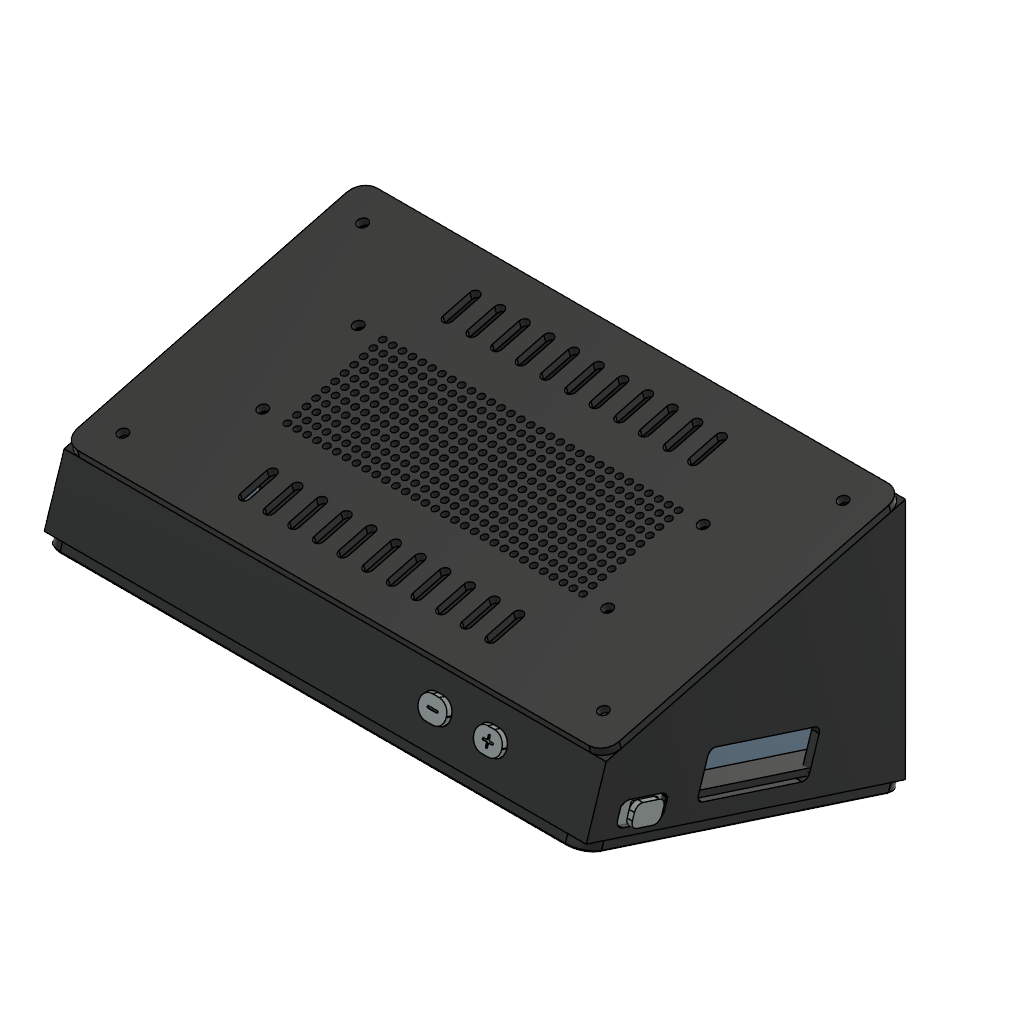
NP2-case-v03 (Autodesk Fusion 360 design; units mm, degrees)
Autodesk Fusion 360 part; units mm, degrees
(part 1 of 2)
sketch "Esboço1" plane through (0, 0, 0) normal (0, 0, 1) x (1, 0, 0) in component "01 / Moldura fina / microfones frontais"
  line L0 (-82, -55) -> (82, -55)
  line L1 (88, -49) -> (88, 49)
  line L2 (82, 55) -> (-82, 55)
  line L3 (-88, 49) -> (-88, -49)
  arc A0 (82, -55) -> (88, -49) centre (82, -49) ccw
  arc A1 (88, 49) -> (82, 55) centre (82, 49) ccw
  arc A2 (-82, 55) -> (-88, 49) centre (-82, 49) ccw
  arc A3 (-88, -49) -> (-82, -55) centre (-82, -49) ccw
extrude "Frente 176 x 110 R6" add sketch "Esboço1" against normal blind 3 makes body 1 in component "01 / Moldura fina / microfones frontais"
fillet "Borda de toque suave" radius 0.5 64 edges at (0, -55, 0) (86.2426, -53.2426, 0) (88, 0, 0) (86.2426, 53.2426, 0) (0, 55, 0) (-86.2426, 53.2426, 0) (-88, 0, 0) (-86.2426, -53.2426, 0) (86.2426, -53.2426, 0) (88, 0, 0) (86.2426, 53.2426, 0) (0, 55, 0) (-86.2426, 53.2426, 0) (-88, 0, 0) (-86.2426, -53.2426, 0) (0, -55, 0) (88, 0, 0) (86.2426, 53.2426, 0) (0, 55, 0) (-86.2426, 53.2426, 0) (-88, 0, 0) (-86.2426, -53.2426, 0) (0, -55, 0) (86.2426, -53.2426, 0) (86.2426, 53.2426, 0) (0, 55, 0) (-86.2426, 53.2426, 0) (-88, 0, 0) (-86.2426, -53.2426, 0) (0, -55, 0) (86.2426, -53.2426, 0) (88, 0, 0) (0, 55, 0) (-86.2426, 53.2426, 0) (-88, 0, 0) (-86.2426, -53.2426, 0) (0, -55, 0) (86.2426, -53.2426, 0) (88, 0, 0) (86.2426, 53.2426, 0) (-86.2426, 53.2426, 0) (-88, 0, 0) (-86.2426, -53.2426, 0) (0, -55, 0) (86.2426, -53.2426, 0) (88, 0, 0) (86.2426, 53.2426, 0) (0, 55, 0) (-88, 0, 0) (-86.2426, -53.2426, 0) (0, -55, 0) (86.2426, -53.2426, 0) (88, 0, 0) (86.2426, 53.2426, 0) (0, 55, 0) (-86.2426, 53.2426, 0) (-86.2426, -53.2426, 0) (0, -55, 0) (86.2426, -53.2426, 0) (88, 0, 0) (86.2426, 53.2426, 0) (0, 55, 0) (-86.2426, 53.2426, 0) (-88, 0, 0) on bodies 1 in component "01 / Moldura fina / microfones frontais"
ref_plane "Plano de trabalho1" through (0, 0, 0.1) normal (0, 0, 1) x (1, 0, 0) in component "01 / Moldura fina / microfones frontais"
sketch "Esboço2" plane through (0, 0, 0.1) normal (0, 0, 1) x (1, 0, 0) in component "01 / Moldura fina / microfones frontais"
  line L0 (-81.84, -49.885) -> (81.84, -49.885)
  line L1 (82.44, -49.285) -> (82.44, 49.285)
  line L2 (81.84, 49.885) -> (-81.84, 49.885)
  line L3 (-82.44, 49.285) -> (-82.44, -49.285)
  arc A0 (81.84, -49.885) -> (82.44, -49.285) centre (81.84, -49.285) ccw
  arc A1 (82.44, 49.285) -> (81.84, 49.885) centre (81.84, 49.285) ccw
  arc A2 (-81.84, 49.885) -> (-82.44, 49.285) centre (-81.84, 49.285) ccw
  arc A3 (-82.44, -49.285) -> (-81.84, -49.885) centre (-81.84, -49.285) ccw
extrude "Janela vidro / folga 0.3 mm por lado" cut sketch "Esboço2" against normal blind 3.3 bodies 1 in component "01 / Moldura fina / microfones frontais"
ref_plane "Plano de trabalho2" through (0, 0, 0.1) normal (0, 0, 1) x (1, 0, 0) in component "01 / Moldura fina / microfones frontais"
sketch "Esboço3" plane through (0, 0, 0.1) normal (0, 0, 1) x (1, 0, 0) in component "01 / Moldura fina / microfones frontais"
  circle A0 centre (-68, -51) radius 0.8
  circle A1 centre (73, -51) radius 0.8
extrude "MIC 1 e MIC 2 / borda inferior" cut sketch "Esboço3" against normal blind 3.3 bodies 1 in component "01 / Moldura fina / microfones frontais"
ref_plane "Plano de trabalho1" through (0, 0, -0.65) normal (0, 0, 1) x (1, 0, 0) in component "REF / Vidro 164.28 x 99.17 / area ativa assimetrica"
sketch "Esboço1 (2)" plane through (0, 0, -0.65) normal (0, 0, 1) x (1, 0, 0) in component "REF / Vidro 164.28 x 99.17 / area ativa assimetrica"
  line L0 (-81.89, -49.585) -> (81.89, -49.585)
  line L1 (82.14, -49.335) -> (82.14, 49.335)
  line L2 (81.89, 49.585) -> (-81.89, 49.585)
  line L3 (-82.14, 49.335) -> (-82.14, -49.335)
  arc A0 (81.89, -49.585) -> (82.14, -49.335) centre (81.89, -49.335) ccw
  arc A1 (82.14, 49.335) -> (81.89, 49.585) centre (81.89, 49.335) ccw
  arc A2 (-81.89, 49.585) -> (-82.14, 49.335) centre (-81.89, 49.335) ccw
  arc A3 (-82.14, -49.335) -> (-81.89, -49.585) centre (-81.89, -49.335) ccw
extrude "Vidro do display" add sketch "Esboço1 (2)" against normal blind 2.15 separate body makes body 2 in component "REF / Vidro 164.28 x 99.17 / area ativa assimetrica"
ref_plane "Plano de trabalho2" through (0, 0, -0.6) normal (0, 0, 1) x (1, 0, 0) in component "REF / Vidro 164.28 x 99.17 / area ativa assimetrica"
sketch "Esboço2 (2)" plane through (0, 0, -0.6) normal (0, 0, 1) x (1, 0, 0) in component "REF / Vidro 164.28 x 99.17 / area ativa assimetrica"
  line L0 (-78.985, -40.855) -> (75.395, -40.855)
  line L1 (75.495, -40.755) -> (75.495, 45.465)
  line L2 (75.395, 45.565) -> (-78.985, 45.565)
  line L3 (-79.085, 45.465) -> (-79.085, -40.755)
  arc A0 (75.395, -40.855) -> (75.495, -40.755) centre (75.395, -40.755) ccw
  arc A1 (75.495, 45.465) -> (75.395, 45.565) centre (75.395, 45.465) ccw
  arc A2 (-78.985, 45.565) -> (-79.085, 45.465) centre (-78.985, 45.465) ccw
  arc A3 (-79.085, -40.755) -> (-78.985, -40.855) centre (-78.985, -40.755) ccw
extrude "Area ativa 154.58 x 86.42" add sketch "Esboço2 (2)" against normal blind 0.04 separate body makes body 3 in component "REF / Vidro 164.28 x 99.17 / area ativa assimetrica"
ref_plane "Plano de trabalho1" through (-88, 0, 0) normal (1, 0, 0) x (0, 1, 0) in component "02 / Corpo em cunha / apoio direto na mesa"
sketch "Esboço1 (3)" plane through (-88, 0, 0) normal (1, 0, 0) x (0, 0, -1) in component "02 / Corpo em cunha / apoio direto na mesa"
  line L0 (3, -54) -> (3, 55)
  line L1 (3, 55) -> (24, 55)
  line L2 (24, 55) -> (78, -29.6563)
  line L3 (78, -29.6563) -> (3, -54)
extrude "Volume externo da cunha" add sketch "Esboço1 (3)" along normal blind 176 separate body makes body 4 in component "02 / Corpo em cunha / apoio direto na mesa"
shell "Paredes 2.4 / frente e traseira abertas" thickness 2.4 removed faces 2 at (-29.3333, -17.6667, -3) at (-29.3333, 26.7812, -42) on bodies 4 in component "02 / Corpo em cunha / apoio direto na mesa"
ref_plane "Plano de trabalho2" through (-88.1, 0, 0) normal (1, 0, 0) x (0, 1, 0) in component "02 / Corpo em cunha / apoio direto na mesa"
sketch "Esboço2 (3)" plane through (-88.1, 0, 0) normal (1, 0, 0) x (0, 0, -1) in component "02 / Corpo em cunha / apoio direto na mesa"
  line L0 (10, -19) -> (20, -19)
  line L1 (22, -17) -> (22, 17)
  line L2 (20, 19) -> (10, 19)
  line L3 (8, 17) -> (8, -17)
  arc A0 (20, -19) -> (22, -17) centre (20, -17) ccw
  arc A1 (22, 17) -> (20, 19) centre (20, 17) ccw
  arc A2 (10, 19) -> (8, 17) centre (10, 17) ccw
  arc A3 (8, -17) -> (10, -19) centre (10, -17) ccw
extrude "Acesso lateral / USB e expansao" cut sketch "Esboço2 (3)" along normal blind 2.8 bodies 4 in component "02 / Corpo em cunha / apoio direto na mesa"
ref_plane "Plano de trabalho3" through (88.1, 0, 0) normal (1, 0, 0) x (0, 1, 0) in component "02 / Corpo em cunha / apoio direto na mesa"
sketch "Esboço3 (2)" plane through (88.1, 0, 0) normal (1, 0, 0) x (0, 0, -1) in component "02 / Corpo em cunha / apoio direto na mesa"
  line L0 (10, -19) -> (20, -19)
  line L1 (22, -17) -> (22, 17)
  line L2 (20, 19) -> (10, 19)
  line L3 (8, 17) -> (8, -17)
  arc A0 (20, -19) -> (22, -17) centre (20, -17) ccw
  arc A1 (22, 17) -> (20, 19) centre (20, 17) ccw
  arc A2 (10, 19) -> (8, 17) centre (10, 17) ccw
  arc A3 (8, -17) -> (10, -19) centre (10, -17) ccw
extrude "Acesso lateral / USB e expansao (1)" cut sketch "Esboço3 (2)" against normal blind 2.8 bodies 4 in component "02 / Corpo em cunha / apoio direto na mesa"
ref_plane "Plano de trabalho4" through (0, 55.1, 0) normal (0, 1, 0) x (0, 0, 1) in component "02 / Corpo em cunha / apoio direto na mesa"
sketch "Esboço4" plane through (0, 55.1, 0) normal (0, 1, 0) x (1, 0, 0) in component "02 / Corpo em cunha / apoio direto na mesa"
  line L0 (34.8, 10.2) -> (37.2, 10.2)
  line L1 (40.8, 13.8) -> (40.8, 14.2)
  line L2 (37.2, 17.8) -> (34.8, 17.8)
  line L3 (31.2, 14.2) -> (31.2, 13.8)
  arc A0 (37.2, 10.2) -> (40.8, 13.8) centre (37.2, 13.8) ccw
  arc A1 (40.8, 14.2) -> (37.2, 17.8) centre (37.2, 14.2) ccw
  arc A2 (34.8, 17.8) -> (31.2, 14.2) centre (34.8, 14.2) ccw
  arc A3 (31.2, 13.8) -> (34.8, 10.2) centre (34.8, 13.8) ccw
extrude "Janela tecla volume" cut sketch "Esboço4" against normal blind 2.7 bodies 4 in component "02 / Corpo em cunha / apoio direto na mesa"
ref_plane "Plano de trabalho5" through (0, 55.1, 0) normal (0, 1, 0) x (0, 0, 1) in component "02 / Corpo em cunha / apoio direto na mesa"
sketch "Esboço5" plane through (0, 55.1, 0) normal (0, 1, 0) x (1, 0, 0) in component "02 / Corpo em cunha / apoio direto na mesa"
  line L0 (52.8, 10.2) -> (55.2, 10.2)
  line L1 (58.8, 13.8) -> (58.8, 14.2)
  line L2 (55.2, 17.8) -> (52.8, 17.8)
  line L3 (49.2, 14.2) -> (49.2, 13.8)
  arc A0 (55.2, 10.2) -> (58.8, 13.8) centre (55.2, 13.8) ccw
  arc A1 (58.8, 14.2) -> (55.2, 17.8) centre (55.2, 14.2) ccw
  arc A2 (52.8, 17.8) -> (49.2, 14.2) centre (52.8, 14.2) ccw
  arc A3 (49.2, 13.8) -> (52.8, 10.2) centre (52.8, 13.8) ccw
extrude "Janela tecla volume (1)" cut sketch "Esboço5" against normal blind 2.7 bodies 4 in component "02 / Corpo em cunha / apoio direto na mesa"
ref_plane "Plano de trabalho6" through (88.1, 0, 0) normal (1, 0, 0) x (0, 1, 0) in component "02 / Corpo em cunha / apoio direto na mesa"
sketch "Esboço6" plane through (88.1, 0, 0) normal (1, 0, 0) x (0, 0, -1) in component "02 / Corpo em cunha / apoio direto na mesa"
  line L0 (7.8, 29.82) -> (10.2, 29.82)
  line L1 (12.6, 32.22) -> (12.6, 43.42)
  line L2 (10.2, 45.82) -> (7.8, 45.82)
  line L3 (5.4, 43.42) -> (5.4, 32.22)
  arc A0 (10.2, 29.82) -> (12.6, 32.22) centre (10.2, 32.22) ccw
  arc A1 (12.6, 43.42) -> (10.2, 45.82) centre (10.2, 43.42) ccw
  arc A2 (7.8, 45.82) -> (5.4, 43.42) centre (7.8, 43.42) ccw
  arc A3 (5.4, 32.22) -> (7.8, 29.82) centre (7.8, 32.22) ccw
extrude "Janela chave ON OFF original" cut sketch "Esboço6" against normal blind 2.7 bodies 4 in component "02 / Corpo em cunha / apoio direto na mesa"
sketch "Esboço1 (4)" plane through (0, 0, 0) normal (0, 0, 1) x (1, 0, 0) in component "03 / Tampa traseira / grelha alto-falante + ventilacao"
  point P0 (-10, 0)
  point P1 (10, 0)
  point P2 (0, 20)
ref_plane "Plano de trabalho1" through (-10, 0, -59.0831) normal (0, -0.537781, 0.843084) x (1, 0, 0) in component "03 / Tampa traseira / grelha alto-falante + ventilacao"
sketch "Esboço2 (4)" plane through (0, 26.788, -41.9957) normal (0, -0.537781, 0.843084) x (1, 0, 0) in component "03 / Tampa traseira / grelha alto-falante + ventilacao"
  line L0 (-83, -66.9497) -> (83, -66.9497)
  line L1 (88, -61.9497) -> (88, 28.4629)
  line L2 (83, 33.4629) -> (-83, 33.4629)
  line L3 (-88, 28.4629) -> (-88, -61.9497)
  arc A0 (83, -66.9497) -> (88, -61.9497) centre (83, -61.9497) ccw
  arc A1 (88, 28.4629) -> (83, 33.4629) centre (83, 28.4629) ccw
  arc A2 (-83, 33.4629) -> (-88, 28.4629) centre (-83, 28.4629) ccw
  arc A3 (-88, -61.9497) -> (-83, -66.9497) centre (-83, -61.9497) ccw
extrude "Tampa traseira removivel" add sketch "Esboço2 (4)" against normal blind 2.4 separate body makes body 5 in component "03 / Tampa traseira / grelha alto-falante + ventilacao"
sketch "Esboço3 (3)" plane through (0, 0, 0) normal (0, 0, 1) x (1, 0, 0) in component "03 / Tampa traseira / grelha alto-falante + ventilacao"
  point P0 (-10, 0)
  point P1 (10, 0)
  point P2 (0, 20)
ref_plane "Plano de trabalho2" through (-10, 0, -59.0831) normal (0, -0.537781, 0.843084) x (1, 0, 0) in component "03 / Tampa traseira / grelha alto-falante + ventilacao"
ref_plane "Plano de trabalho3" through (-10, -0.0538, -58.9987) normal (0, -0.537781, 0.843084) x (1, 0, 0) in component "03 / Tampa traseira / grelha alto-falante + ventilacao"
sketch "Esboço4 (2)" plane through (0, 26.7342, -41.9114) normal (0, -0.537781, 0.843084) x (1, 0, 0) in component "03 / Tampa traseira / grelha alto-falante + ventilacao"
  circle A0 centre (-35.2, -24.7434) radius 1
  circle A1 centre (-32, -24.7434) radius 1
  circle A2 centre (-28.8, -24.7434) radius 1
  circle A3 centre (-25.6, -24.7434) radius 1
  circle A4 centre (-22.4, -24.7434) radius 1
  circle A5 centre (-19.2, -24.7434) radius 1
  circle A6 centre (-16, -24.7434) radius 1
  circle A7 centre (-12.8, -24.7434) radius 1
  circle A8 centre (-9.6, -24.7434) radius 1
  circle A9 centre (-6.4, -24.7434) radius 1
  circle A10 centre (-3.2, -24.7434) radius 1
  circle A11 centre (0, -24.7434) radius 1
  circle A12 centre (3.2, -24.7434) radius 1
  circle A13 centre (6.4, -24.7434) radius 1
  circle A14 centre (9.6, -24.7434) radius 1
  circle A15 centre (12.8, -24.7434) radius 1
  circle A16 centre (16, -24.7434) radius 1
  circle A17 centre (19.2, -24.7434) radius 1
  circle A18 centre (22.4, -24.7434) radius 1
  circle A19 centre (25.6, -24.7434) radius 1
  circle A20 centre (28.8, -24.7434) radius 1
  circle A21 centre (32, -24.7434) radius 1
  circle A22 centre (35.2, -24.7434) radius 1
  circle A23 centre (-35.2, -21.5434) radius 1
  circle A24 centre (-32, -21.5434) radius 1
  circle A25 centre (-28.8, -21.5434) radius 1
  circle A26 centre (-25.6, -21.5434) radius 1
  circle A27 centre (-22.4, -21.5434) radius 1
  circle A28 centre (-19.2, -21.5434) radius 1
  circle A29 centre (-16, -21.5434) radius 1
  circle A30 centre (-12.8, -21.5434) radius 1
  circle A31 centre (-9.6, -21.5434) radius 1
  circle A32 centre (-6.4, -21.5434) radius 1
  circle A33 centre (-3.2, -21.5434) radius 1
  circle A34 centre (0, -21.5434) radius 1
  circle A35 centre (3.2, -21.5434) radius 1
  circle A36 centre (6.4, -21.5434) radius 1
  circle A37 centre (9.6, -21.5434) radius 1
  circle A38 centre (12.8, -21.5434) radius 1
  circle A39 centre (16, -21.5434) radius 1
  circle A40 centre (19.2, -21.5434) radius 1
  circle A41 centre (22.4, -21.5434) radius 1
  circle A42 centre (25.6, -21.5434) radius 1
  circle A43 centre (28.8, -21.5434) radius 1
  circle A44 centre (32, -21.5434) radius 1
  circle A45 centre (35.2, -21.5434) radius 1
  circle A46 centre (-35.2, -18.3434) radius 1
  circle A47 centre (-32, -18.3434) radius 1
  circle A48 centre (-28.8, -18.3434) radius 1
  circle A49 centre (-25.6, -18.3434) radius 1
  circle A50 centre (-22.4, -18.3434) radius 1
  circle A51 centre (-19.2, -18.3434) radius 1
  circle A52 centre (-16, -18.3434) radius 1
  circle A53 centre (-12.8, -18.3434) radius 1
  circle A54 centre (-9.6, -18.3434) radius 1
  circle A55 centre (-6.4, -18.3434) radius 1
  circle A56 centre (-3.2, -18.3434) radius 1
  circle A57 centre (0, -18.3434) radius 1
  circle A58 centre (3.2, -18.3434) radius 1
  circle A59 centre (6.4, -18.3434) radius 1
  circle A60 centre (9.6, -18.3434) radius 1
  circle A61 centre (12.8, -18.3434) radius 1
  circle A62 centre (16, -18.3434) radius 1
  circle A63 centre (19.2, -18.3434) radius 1
  circle A64 centre (22.4, -18.3434) radius 1
  circle A65 centre (25.6, -18.3434) radius 1
  circle A66 centre (28.8, -18.3434) radius 1
  circle A67 centre (32, -18.3434) radius 1
  circle A68 centre (35.2, -18.3434) radius 1
  circle A69 centre (-35.2, -15.1434) radius 1
  circle A70 centre (-32, -15.1434) radius 1
  circle A71 centre (-28.8, -15.1434) radius 1
  circle A72 centre (-25.6, -15.1434) radius 1
  circle A73 centre (-22.4, -15.1434) radius 1
  circle A74 centre (-19.2, -15.1434) radius 1
  circle A75 centre (-16, -15.1434) radius 1
  circle A76 centre (-12.8, -15.1434) radius 1
  circle A77 centre (-9.6, -15.1434) radius 1
  circle A78 centre (-6.4, -15.1434) radius 1
  circle A79 centre (-3.2, -15.1434) radius 1
  circle A80 centre (0, -15.1434) radius 1
  circle A81 centre (3.2, -15.1434) radius 1
  circle A82 centre (6.4, -15.1434) radius 1
  circle A83 centre (9.6, -15.1434) radius 1
  circle A84 centre (12.8, -15.1434) radius 1
  circle A85 centre (16, -15.1434) radius 1
  circle A86 centre (19.2, -15.1434) radius 1
  circle A87 centre (22.4, -15.1434) radius 1
  circle A88 centre (25.6, -15.1434) radius 1
  circle A89 centre (28.8, -15.1434) radius 1
  circle A90 centre (32, -15.1434) radius 1
  circle A91 centre (35.2, -15.1434) radius 1
  circle A92 centre (-35.2, -11.9434) radius 1
  circle A93 centre (-32, -11.9434) radius 1
  circle A94 centre (-28.8, -11.9434) radius 1
  circle A95 centre (-25.6, -11.9434) radius 1
  circle A96 centre (-22.4, -11.9434) radius 1
  circle A97 centre (-19.2, -11.9434) radius 1
  circle A98 centre (-16, -11.9434) radius 1
  circle A99 centre (-12.8, -11.9434) radius 1
  circle A100 centre (-9.6, -11.9434) radius 1
  circle A101 centre (-6.4, -11.9434) radius 1
  circle A102 centre (-3.2, -11.9434) radius 1
  circle A103 centre (0, -11.9434) radius 1
  circle A104 centre (3.2, -11.9434) radius 1
  circle A105 centre (6.4, -11.9434) radius 1
  circle A106 centre (9.6, -11.9434) radius 1
  circle A107 centre (12.8, -11.9434) radius 1
  circle A108 centre (16, -11.9434) radius 1
  circle A109 centre (19.2, -11.9434) radius 1
  circle A110 centre (22.4, -11.9434) radius 1
  circle A111 centre (25.6, -11.9434) radius 1
  circle A112 centre (28.8, -11.9434) radius 1
  circle A113 centre (32, -11.9434) radius 1
  circle A114 centre (35.2, -11.9434) radius 1
  circle A115 centre (-35.2, -8.7434) radius 1
  circle A116 centre (-32, -8.7434) radius 1
  circle A117 centre (-28.8, -8.7434) radius 1
  circle A118 centre (-25.6, -8.7434) radius 1
  circle A119 centre (-22.4, -8.7434) radius 1
  circle A120 centre (-19.2, -8.7434) radius 1
  circle A121 centre (-16, -8.7434) radius 1
  circle A122 centre (-12.8, -8.7434) radius 1
  circle A123 centre (-9.6, -8.7434) radius 1
  circle A124 centre (-6.4, -8.7434) radius 1
  circle A125 centre (-3.2, -8.7434) radius 1
  circle A126 centre (0, -8.7434) radius 1
  circle A127 centre (3.2, -8.7434) radius 1
  circle A128 centre (6.4, -8.7434) radius 1
  circle A129 centre (9.6, -8.7434) radius 1
  circle A130 centre (12.8, -8.7434) radius 1
  circle A131 centre (16, -8.7434) radius 1
  circle A132 centre (19.2, -8.7434) radius 1
  circle A133 centre (22.4, -8.7434) radius 1
  circle A134 centre (25.6, -8.7434) radius 1
  circle A135 centre (28.8, -8.7434) radius 1
  circle A136 centre (32, -8.7434) radius 1
  circle A137 centre (35.2, -8.7434) radius 1
sketch "Esboço5 (2)" plane through (0, 0, 0) normal (0, 0, 1) x (1, 0, 0) in component "03 / Tampa traseira / grelha alto-falante + ventilacao"
  point P0 (-10, 0)
  point P1 (10, 0)
  point P2 (0, 20)
ref_plane "Plano de trabalho4" through (-10, 0, -59.0831) normal (0, -0.537781, 0.843084) x (1, 0, 0) in component "03 / Tampa traseira / grelha alto-falante + ventilacao"
ref_plane "Plano de trabalho5" through (-10, -0.0538, -58.9987) normal (0, -0.537781, 0.843084) x (1, 0, 0) in component "03 / Tampa traseira / grelha alto-falante + ventilacao"
sketch "Esboço6 (2)" plane through (0, 26.7342, -41.9114) normal (0, -0.537781, 0.843084) x (1, 0, 0) in component "03 / Tampa traseira / grelha alto-falante + ventilacao"
  line L0 (-40, -56.7434) -> (-40, -56.7434)
  line L1 (-38.5, -55.2434) -> (-38.5, -46.2434)
  line L2 (-40, -44.7434) -> (-40, -44.7434)
  line L3 (-41.5, -46.2434) -> (-41.5, -55.2434)
  arc A0 (-40, -56.7434) -> (-38.5, -55.2434) centre (-40, -55.2434) ccw
  arc A1 (-38.5, -46.2434) -> (-40, -44.7434) centre (-40, -46.2434) ccw
  arc A2 (-40, -44.7434) -> (-41.5, -46.2434) centre (-40, -46.2434) ccw
  arc A3 (-41.5, -55.2434) -> (-40, -56.7434) centre (-40, -55.2434) ccw
  line L4 (-32, -56.7434) -> (-32, -56.7434)
  line L5 (-30.5, -55.2434) -> (-30.5, -46.2434)
  line L6 (-32, -44.7434) -> (-32, -44.7434)
  line L7 (-33.5, -46.2434) -> (-33.5, -55.2434)
  arc A4 (-32, -56.7434) -> (-30.5, -55.2434) centre (-32, -55.2434) ccw
  arc A5 (-30.5, -46.2434) -> (-32, -44.7434) centre (-32, -46.2434) ccw
  arc A6 (-32, -44.7434) -> (-33.5, -46.2434) centre (-32, -46.2434) ccw
  arc A7 (-33.5, -55.2434) -> (-32, -56.7434) centre (-32, -55.2434) ccw
  line L8 (-24, -56.7434) -> (-24, -56.7434)
  line L9 (-22.5, -55.2434) -> (-22.5, -46.2434)
  line L10 (-24, -44.7434) -> (-24, -44.7434)
  line L11 (-25.5, -46.2434) -> (-25.5, -55.2434)
  arc A8 (-24, -56.7434) -> (-22.5, -55.2434) centre (-24, -55.2434) ccw
  arc A9 (-22.5, -46.2434) -> (-24, -44.7434) centre (-24, -46.2434) ccw
  arc A10 (-24, -44.7434) -> (-25.5, -46.2434) centre (-24, -46.2434) ccw
  arc A11 (-25.5, -55.2434) -> (-24, -56.7434) centre (-24, -55.2434) ccw
  line L12 (-16, -56.7434) -> (-16, -56.7434)
  line L13 (-14.5, -55.2434) -> (-14.5, -46.2434)
  line L14 (-16, -44.7434) -> (-16, -44.7434)
  line L15 (-17.5, -46.2434) -> (-17.5, -55.2434)
  arc A12 (-16, -56.7434) -> (-14.5, -55.2434) centre (-16, -55.2434) ccw
  arc A13 (-14.5, -46.2434) -> (-16, -44.7434) centre (-16, -46.2434) ccw
  arc A14 (-16, -44.7434) -> (-17.5, -46.2434) centre (-16, -46.2434) ccw
  arc A15 (-17.5, -55.2434) -> (-16, -56.7434) centre (-16, -55.2434) ccw
  line L16 (-8, -56.7434) -> (-8, -56.7434)
  line L17 (-6.5, -55.2434) -> (-6.5, -46.2434)
  line L18 (-8, -44.7434) -> (-8, -44.7434)
  line L19 (-9.5, -46.2434) -> (-9.5, -55.2434)
  arc A16 (-8, -56.7434) -> (-6.5, -55.2434) centre (-8, -55.2434) ccw
  arc A17 (-6.5, -46.2434) -> (-8, -44.7434) centre (-8, -46.2434) ccw
  arc A18 (-8, -44.7434) -> (-9.5, -46.2434) centre (-8, -46.2434) ccw
  arc A19 (-9.5, -55.2434) -> (-8, -56.7434) centre (-8, -55.2434) ccw
  line L20 (0, -56.7434) -> (0, -56.7434)
  line L21 (1.5, -55.2434) -> (1.5, -46.2434)
  line L22 (0, -44.7434) -> (0, -44.7434)
  line L23 (-1.5, -46.2434) -> (-1.5, -55.2434)
  arc A20 (0, -56.7434) -> (1.5, -55.2434) centre (0, -55.2434) ccw
  arc A21 (1.5, -46.2434) -> (0, -44.7434) centre (0, -46.2434) ccw
  arc A22 (0, -44.7434) -> (-1.5, -46.2434) centre (0, -46.2434) ccw
  arc A23 (-1.5, -55.2434) -> (0, -56.7434) centre (0, -55.2434) ccw
  line L24 (8, -56.7434) -> (8, -56.7434)
  line L25 (9.5, -55.2434) -> (9.5, -46.2434)
  line L26 (8, -44.7434) -> (8, -44.7434)
  line L27 (6.5, -46.2434) -> (6.5, -55.2434)
  arc A24 (8, -56.7434) -> (9.5, -55.2434) centre (8, -55.2434) ccw
  arc A25 (9.5, -46.2434) -> (8, -44.7434) centre (8, -46.2434) ccw
  arc A26 (8, -44.7434) -> (6.5, -46.2434) centre (8, -46.2434) ccw
  arc A27 (6.5, -55.2434) -> (8, -56.7434) centre (8, -55.2434) ccw
  line L28 (16, -56.7434) -> (16, -56.7434)
  line L29 (17.5, -55.2434) -> (17.5, -46.2434)
  line L30 (16, -44.7434) -> (16, -44.7434)
  line L31 (14.5, -46.2434) -> (14.5, -55.2434)
  arc A28 (16, -56.7434) -> (17.5, -55.2434) centre (16, -55.2434) ccw
  arc A29 (17.5, -46.2434) -> (16, -44.7434) centre (16, -46.2434) ccw
  arc A30 (16, -44.7434) -> (14.5, -46.2434) centre (16, -46.2434) ccw
  arc A31 (14.5, -55.2434) -> (16, -56.7434) centre (16, -55.2434) ccw
  line L32 (24, -56.7434) -> (24, -56.7434)
  line L33 (25.5, -55.2434) -> (25.5, -46.2434)
  line L34 (24, -44.7434) -> (24, -44.7434)
  line L35 (22.5, -46.2434) -> (22.5, -55.2434)
  arc A32 (24, -56.7434) -> (25.5, -55.2434) centre (24, -55.2434) ccw
  arc A33 (25.5, -46.2434) -> (24, -44.7434) centre (24, -46.2434) ccw
  arc A34 (24, -44.7434) -> (22.5, -46.2434) centre (24, -46.2434) ccw
  arc A35 (22.5, -55.2434) -> (24, -56.7434) centre (24, -55.2434) ccw
  line L36 (32, -56.7434) -> (32, -56.7434)
  line L37 (33.5, -55.2434) -> (33.5, -46.2434)
  line L38 (32, -44.7434) -> (32, -44.7434)
  line L39 (30.5, -46.2434) -> (30.5, -55.2434)
  arc A36 (32, -56.7434) -> (33.5, -55.2434) centre (32, -55.2434) ccw
  arc A37 (33.5, -46.2434) -> (32, -44.7434) centre (32, -46.2434) ccw
  arc A38 (32, -44.7434) -> (30.5, -46.2434) centre (32, -46.2434) ccw
  arc A39 (30.5, -55.2434) -> (32, -56.7434) centre (32, -55.2434) ccw
  line L40 (40, -56.7434) -> (40, -56.7434)
  line L41 (41.5, -55.2434) -> (41.5, -46.2434)
  line L42 (40, -44.7434) -> (40, -44.7434)
  line L43 (38.5, -46.2434) -> (38.5, -55.2434)
  arc A40 (40, -56.7434) -> (41.5, -55.2434) centre (40, -55.2434) ccw
  arc A41 (41.5, -46.2434) -> (40, -44.7434) centre (40, -46.2434) ccw
  arc A42 (40, -44.7434) -> (38.5, -46.2434) centre (40, -46.2434) ccw
  arc A43 (38.5, -55.2434) -> (40, -56.7434) centre (40, -55.2434) ccw
  line L44 (-40, 11.2566) -> (-40, 11.2566)
  line L45 (-38.5, 12.7566) -> (-38.5, 21.7566)
  line L46 (-40, 23.2566) -> (-40, 23.2566)
  line L47 (-41.5, 21.7566) -> (-41.5, 12.7566)
  arc A44 (-40, 11.2566) -> (-38.5, 12.7566) centre (-40, 12.7566) ccw
  arc A45 (-38.5, 21.7566) -> (-40, 23.2566) centre (-40, 21.7566) ccw
  arc A46 (-40, 23.2566) -> (-41.5, 21.7566) centre (-40, 21.7566) ccw
  arc A47 (-41.5, 12.7566) -> (-40, 11.2566) centre (-40, 12.7566) ccw
  line L48 (-32, 11.2566) -> (-32, 11.2566)
  line L49 (-30.5, 12.7566) -> (-30.5, 21.7566)
  line L50 (-32, 23.2566) -> (-32, 23.2566)
  line L51 (-33.5, 21.7566) -> (-33.5, 12.7566)
  arc A48 (-32, 11.2566) -> (-30.5, 12.7566) centre (-32, 12.7566) ccw
  arc A49 (-30.5, 21.7566) -> (-32, 23.2566) centre (-32, 21.7566) ccw
  arc A50 (-32, 23.2566) -> (-33.5, 21.7566) centre (-32, 21.7566) ccw
  arc A51 (-33.5, 12.7566) -> (-32, 11.2566) centre (-32, 12.7566) ccw
  line L52 (-24, 11.2566) -> (-24, 11.2566)
  line L53 (-22.5, 12.7566) -> (-22.5, 21.7566)
  line L54 (-24, 23.2566) -> (-24, 23.2566)
  line L55 (-25.5, 21.7566) -> (-25.5, 12.7566)
  arc A52 (-24, 11.2566) -> (-22.5, 12.7566) centre (-24, 12.7566) ccw
  arc A53 (-22.5, 21.7566) -> (-24, 23.2566) centre (-24, 21.7566) ccw
  arc A54 (-24, 23.2566) -> (-25.5, 21.7566) centre (-24, 21.7566) ccw
  arc A55 (-25.5, 12.7566) -> (-24, 11.2566) centre (-24, 12.7566) ccw
  line L56 (-16, 11.2566) -> (-16, 11.2566)
  line L57 (-14.5, 12.7566) -> (-14.5, 21.7566)
  line L58 (-16, 23.2566) -> (-16, 23.2566)
  line L59 (-17.5, 21.7566) -> (-17.5, 12.7566)
  arc A56 (-16, 11.2566) -> (-14.5, 12.7566) centre (-16, 12.7566) ccw
  arc A57 (-14.5, 21.7566) -> (-16, 23.2566) centre (-16, 21.7566) ccw
  arc A58 (-16, 23.2566) -> (-17.5, 21.7566) centre (-16, 21.7566) ccw
  arc A59 (-17.5, 12.7566) -> (-16, 11.2566) centre (-16, 12.7566) ccw
  line L60 (-8, 11.2566) -> (-8, 11.2566)
  line L61 (-6.5, 12.7566) -> (-6.5, 21.7566)
  line L62 (-8, 23.2566) -> (-8, 23.2566)
  line L63 (-9.5, 21.7566) -> (-9.5, 12.7566)
  arc A60 (-8, 11.2566) -> (-6.5, 12.7566) centre (-8, 12.7566) ccw
  arc A61 (-6.5, 21.7566) -> (-8, 23.2566) centre (-8, 21.7566) ccw
  arc A62 (-8, 23.2566) -> (-9.5, 21.7566) centre (-8, 21.7566) ccw
  arc A63 (-9.5, 12.7566) -> (-8, 11.2566) centre (-8, 12.7566) ccw
  line L64 (0, 11.2566) -> (0, 11.2566)
  line L65 (1.5, 12.7566) -> (1.5, 21.7566)
  line L66 (0, 23.2566) -> (0, 23.2566)
  line L67 (-1.5, 21.7566) -> (-1.5, 12.7566)
  arc A64 (0, 11.2566) -> (1.5, 12.7566) centre (0, 12.7566) ccw
  arc A65 (1.5, 21.7566) -> (0, 23.2566) centre (0, 21.7566) ccw
  arc A66 (0, 23.2566) -> (-1.5, 21.7566) centre (0, 21.7566) ccw
  arc A67 (-1.5, 12.7566) -> (0, 11.2566) centre (0, 12.7566) ccw
  line L68 (8, 11.2566) -> (8, 11.2566)
  line L69 (9.5, 12.7566) -> (9.5, 21.7566)
  line L70 (8, 23.2566) -> (8, 23.2566)
  line L71 (6.5, 21.7566) -> (6.5, 12.7566)
  arc A68 (8, 11.2566) -> (9.5, 12.7566) centre (8, 12.7566) ccw
  arc A69 (9.5, 21.7566) -> (8, 23.2566) centre (8, 21.7566) ccw
  arc A70 (8, 23.2566) -> (6.5, 21.7566) centre (8, 21.7566) ccw
  arc A71 (6.5, 12.7566) -> (8, 11.2566) centre (8, 12.7566) ccw
  line L72 (16, 11.2566) -> (16, 11.2566)
  line L73 (17.5, 12.7566) -> (17.5, 21.7566)
  line L74 (16, 23.2566) -> (16, 23.2566)
  line L75 (14.5, 21.7566) -> (14.5, 12.7566)
  arc A72 (16, 11.2566) -> (17.5, 12.7566) centre (16, 12.7566) ccw
  arc A73 (17.5, 21.7566) -> (16, 23.2566) centre (16, 21.7566) ccw
  arc A74 (16, 23.2566) -> (14.5, 21.7566) centre (16, 21.7566) ccw
  arc A75 (14.5, 12.7566) -> (16, 11.2566) centre (16, 12.7566) ccw
  line L76 (24, 11.2566) -> (24, 11.2566)
  line L77 (25.5, 12.7566) -> (25.5, 21.7566)
  line L78 (24, 23.2566) -> (24, 23.2566)
  line L79 (22.5, 21.7566) -> (22.5, 12.7566)
  arc A76 (24, 11.2566) -> (25.5, 12.7566) centre (24, 12.7566) ccw
  arc A77 (25.5, 21.7566) -> (24, 23.2566) centre (24, 21.7566) ccw
  arc A78 (24, 23.2566) -> (22.5, 21.7566) centre (24, 21.7566) ccw
  arc A79 (22.5, 12.7566) -> (24, 11.2566) centre (24, 12.7566) ccw
  line L80 (32, 11.2566) -> (32, 11.2566)
  line L81 (33.5, 12.7566) -> (33.5, 21.7566)
  line L82 (32, 23.2566) -> (32, 23.2566)
  line L83 (30.5, 21.7566) -> (30.5, 12.7566)
  arc A80 (32, 11.2566) -> (33.5, 12.7566) centre (32, 12.7566) ccw
  arc A81 (33.5, 21.7566) -> (32, 23.2566) centre (32, 21.7566) ccw
  arc A82 (32, 23.2566) -> (30.5, 21.7566) centre (32, 21.7566) ccw
  arc A83 (30.5, 12.7566) -> (32, 11.2566) centre (32, 12.7566) ccw
  line L84 (40, 11.2566) -> (40, 11.2566)
  line L85 (41.5, 12.7566) -> (41.5, 21.7566)
  line L86 (40, 23.2566) -> (40, 23.2566)
  line L87 (38.5, 21.7566) -> (38.5, 12.7566)
  arc A84 (40, 11.2566) -> (41.5, 12.7566) centre (40, 12.7566) ccw
  arc A85 (41.5, 21.7566) -> (40, 23.2566) centre (40, 21.7566) ccw
  arc A86 (40, 23.2566) -> (38.5, 21.7566) centre (40, 21.7566) ccw
  arc A87 (38.5, 12.7566) -> (40, 11.2566) centre (40, 12.7566) ccw
extrude "22 fendas de ventilacao" cut sketch "Esboço6 (2)" against normal blind 2.7 bodies 5 in component "03 / Tampa traseira / grelha alto-falante + ventilacao"
sketch "Esboço7" plane through (0, 0, 0) normal (0, 0, 1) x (1, 0, 0) in component "03 / Tampa traseira / grelha alto-falante + ventilacao"
  point P0 (-10, 0)
  point P1 (10, 0)
  point P2 (0, 20)
ref_plane "Plano de trabalho6" through (-10, 0, -59.0831) normal (0, -0.537781, 0.843084) x (1, 0, 0) in component "03 / Tampa traseira / grelha alto-falante + ventilacao"
ref_plane "Plano de trabalho7" through (-10, -0.0538, -58.9987) normal (0, -0.537781, 0.843084) x (1, 0, 0) in component "03 / Tampa traseira / grelha alto-falante + ventilacao"
sketch "Esboço8" plane through (0, 26.7342, -41.9114) normal (0, -0.537781, 0.843084) x (1, 0, 0) in component "03 / Tampa traseira / grelha alto-falante + ventilacao"
  circle A0 centre (-78, -56.9497) radius 1.6
  circle A1 centre (-78, 23.4629) radius 1.6
  circle A2 centre (78, -56.9497) radius 1.6
  circle A3 centre (78, 23.4629) radius 1.6
extrude "4 furos M3 tampa / diametro a validar" cut sketch "Esboço8" against normal blind 2.7 bodies 5 in component "03 / Tampa traseira / grelha alto-falante + ventilacao"
ref_plane "Plano de trabalho1" through (0, 0, -6) normal (0, 0, 1) x (1, 0, 0) in component "REF / PCB 164 x 97 / pitch furos 156 x 89"
sketch "Esboço1 (5)" plane through (0, 0, -6) normal (0, 0, 1) x (1, 0, 0) in component "REF / PCB 164 x 97 / pitch furos 156 x 89"
  line L0 (-81, -48.5) -> (81, -48.5)
  line L1 (82, -47.5) -> (82, 47.5)
  line L2 (81, 48.5) -> (-81, 48.5)
  line L3 (-82, 47.5) -> (-82, -47.5)
  arc A0 (81, -48.5) -> (82, -47.5) centre (81, -47.5) ccw
  arc A1 (82, 47.5) -> (81, 48.5) centre (81, 47.5) ccw
  arc A2 (-81, 48.5) -> (-82, 47.5) centre (-81, 47.5) ccw
  arc A3 (-82, -47.5) -> (-81, -48.5) centre (-81, -47.5) ccw
extrude "PCB / espessura provisÃ³ria" add sketch "Esboço1 (5)" against normal blind 1.6 separate body makes body 6 in component "REF / PCB 164 x 97 / pitch furos 156 x 89"
ref_plane "Plano de trabalho2" through (0, 0, -5.9) normal (0, 0, 1) x (1, 0, 0) in component "REF / PCB 164 x 97 / pitch furos 156 x 89"
sketch "Esboço2 (5)" plane through (0, 0, -5.9) normal (0, 0, 1) x (1, 0, 0) in component "REF / PCB 164 x 97 / pitch furos 156 x 89"
  circle A0 centre (-78, -44.5) radius 1.6
  circle A1 centre (-78, 44.5) radius 1.6
  circle A2 centre (78, -44.5) radius 1.6
  circle A3 centre (78, 44.5) radius 1.6
extrude "Furos PCB / diametro a medir" cut sketch "Esboço2 (5)" against normal blind 1.8 bodies 6 in component "REF / PCB 164 x 97 / pitch furos 156 x 89"
ref_plane "Plano de trabalho1" through (0, 0, -9) normal (0, 0, 1) x (1, 0, 0) in component "04 / Apoios PCB / distancias da foto"
sketch "Esboço1 (6)" plane through (0, 0, -9) normal (0, 0, 1) x (1, 0, 0) in component "04 / Apoios PCB / distancias da foto"
  line L0 (-86, -49) -> (-81, -49)
  line L1 (-79.5, -47.5) -> (-79.5, 47.5)
  line L2 (-81, 49) -> (-86, 49)
  line L3 (-87.5, 47.5) -> (-87.5, -47.5)
  arc A0 (-81, -49) -> (-79.5, -47.5) centre (-81, -47.5) ccw
  arc A1 (-79.5, 47.5) -> (-81, 49) centre (-81, 47.5) ccw
  arc A2 (-86, 49) -> (-87.5, 47.5) centre (-86, 47.5) ccw
  arc A3 (-87.5, -47.5) -> (-86, -49) centre (-86, -47.5) ccw
extrude "Trilho PCB" add sketch "Esboço1 (6)" against normal blind 2 separate body makes body 7 in component "04 / Apoios PCB / distancias da foto"
ref_plane "Plano de trabalho2" through (0, 0, -9) normal (0, 0, 1) x (1, 0, 0) in component "04 / Apoios PCB / distancias da foto"
sketch "Esboço2 (6)" plane through (0, 0, -9) normal (0, 0, 1) x (1, 0, 0) in component "04 / Apoios PCB / distancias da foto"
  line L0 (81, -49) -> (86, -49)
  line L1 (87.5, -47.5) -> (87.5, 47.5)
  line L2 (86, 49) -> (81, 49)
  line L3 (79.5, 47.5) -> (79.5, -47.5)
  arc A0 (86, -49) -> (87.5, -47.5) centre (86, -47.5) ccw
  arc A1 (87.5, 47.5) -> (86, 49) centre (86, 47.5) ccw
  arc A2 (81, 49) -> (79.5, 47.5) centre (81, 47.5) ccw
  arc A3 (79.5, -47.5) -> (81, -49) centre (81, -47.5) ccw
extrude "Trilho PCB (1)" add sketch "Esboço2 (6)" against normal blind 2 separate body makes body 8 in component "04 / Apoios PCB / distancias da foto"
ref_plane "Plano de trabalho3" through (0, 0, -7.6) normal (0, 0, 1) x (1, 0, 0) in component "04 / Apoios PCB / distancias da foto"
sketch "Esboço3 (4)" plane through (0, 0, -7.6) normal (0, 0, 1) x (1, 0, 0) in component "04 / Apoios PCB / distancias da foto"
  circle A0 centre (-78, -44.5) radius 3.5
  circle A1 centre (-78, 44.5) radius 3.5
  circle A2 centre (78, -44.5) radius 3.5
  circle A3 centre (78, 44.5) radius 3.5
extrude "4 apoios placa" add sketch "Esboço3 (4)" against normal blind 3.4 bodies 7 8 in component "04 / Apoios PCB / distancias da foto"
ref_plane "Plano de trabalho4" through (0, 0, -7.5) normal (0, 0, 1) x (1, 0, 0) in component "04 / Apoios PCB / distancias da foto"
sketch "Esboço4 (3)" plane through (0, 0, -7.5) normal (0, 0, 1) x (1, 0, 0) in component "04 / Apoios PCB / distancias da foto"
  circle A0 centre (-78, -44.5) radius 1.1
  circle A1 centre (-78, 44.5) radius 1.1
  circle A2 centre (78, -44.5) radius 1.1
  circle A3 centre (78, 44.5) radius 1.1
extrude "4 pilotos placa / ajustar para M2.5" cut sketch "Esboço4 (3)" against normal blind 3.6 bodies 7 8 in component "04 / Apoios PCB / distancias da foto"
ref_plane "Plano de trabalho5" through (0, 0, -7.8) normal (0, 0, 1) x (1, 0, 0) in component "04 / Apoios PCB / distancias da foto"
sketch "Esboço5 (3)" plane through (0, 0, -7.8) normal (0, 0, 1) x (1, 0, 0) in component "04 / Apoios PCB / distancias da foto"
  line L0 (80, 29.82) -> (88, 29.82)
  line L1 (89, 30.82) -> (89, 44.82)
  line L2 (88, 45.82) -> (80, 45.82)
  line L3 (79, 44.82) -> (79, 30.82)
  arc A0 (88, 29.82) -> (89, 30.82) centre (88, 30.82) ccw
  arc A1 (89, 44.82) -> (88, 45.82) centre (88, 44.82) ccw
  arc A2 (80, 45.82) -> (79, 44.82) centre (80, 44.82) ccw
  arc A3 (79, 30.82) -> (80, 29.82) centre (80, 30.82) ccw
extrude "Alivio para chave original" cut sketch "Esboço5 (3)" against normal blind 3.6 bodies 4 in component "02 / Corpo em cunha / apoio direto na mesa"
extrude "Extrusão5" cut sketch "Esboço5 (3)" against normal blind 3.6 bodies 8 makes body 9 at (79.1081, 47.82, -9.2) in component "04 / Apoios PCB / distancias da foto"
ref_plane "Plano de trabalho1" through (0, 56.4, 0) normal (0, 1, 0) x (0, 0, 1) in component "06 / Volume + e - / teclas no topo"
sketch "Esboço1 (7)" plane through (0, 56.4, 0) normal (0, 1, 0) x (1, 0, 0) in component "06 / Volume + e - / teclas no topo"
  line L0 (34.9, 10.5) -> (37.1, 10.5)
  line L1 (40.5, 13.9) -> (40.5, 14.1)
  line L2 (37.1, 17.5) -> (34.9, 17.5)
  line L3 (31.5, 14.1) -> (31.5, 13.9)
  arc A0 (37.1, 10.5) -> (40.5, 13.9) centre (37.1, 13.9) ccw
  arc A1 (40.5, 14.1) -> (37.1, 17.5) centre (37.1, 14.1) ccw
  arc A2 (34.9, 17.5) -> (31.5, 14.1) centre (34.9, 14.1) ccw
  arc A3 (31.5, 13.9) -> (34.9, 10.5) centre (34.9, 13.9) ccw
extrude "Volume menos" add sketch "Esboço1 (7)" against normal blind 3.1 separate body makes body 10 in component "06 / Volume + e - / teclas no topo"
ref_plane "Plano de trabalho2" through (0, 53.7, 0) normal (0, 1, 0) x (0, 0, 1) in component "06 / Volume + e - / teclas no topo"
sketch "Esboço2 (7)" plane through (0, 53.7, 0) normal (0, 1, 0) x (1, 0, 0) in component "06 / Volume + e - / teclas no topo"
  line L0 (32, 9) -> (40, 9)
  line L1 (42, 11) -> (42, 17)
  line L2 (40, 19) -> (32, 19)
  line L3 (30, 17) -> (30, 11)
  arc A0 (40, 9) -> (42, 11) centre (40, 11) ccw
  arc A1 (42, 17) -> (40, 19) centre (40, 17) ccw
  arc A2 (32, 19) -> (30, 17) centre (32, 17) ccw
  arc A3 (30, 11) -> (32, 9) centre (32, 11) ccw
extrude "Volume menos flange" add sketch "Esboço2 (7)" against normal blind 1.2 bodies 10 in component "06 / Volume + e - / teclas no topo"
ref_plane "Plano de trabalho3" through (0, 53, 0) normal (0, 1, 0) x (0, 0, 1) in component "06 / Volume + e - / teclas no topo"
sketch "Esboço3 (5)" plane through (0, 53, 0) normal (0, 1, 0) x (1, 0, 0) in component "06 / Volume + e - / teclas no topo"
  line L0 (35, 12.5) -> (37, 12.5)
  line L1 (37.5, 13) -> (37.5, 15)
  line L2 (37, 15.5) -> (35, 15.5)
  line L3 (34.5, 15) -> (34.5, 13)
  arc A0 (37, 12.5) -> (37.5, 13) centre (37, 13) ccw
  arc A1 (37.5, 15) -> (37, 15.5) centre (37, 15) ccw
  arc A2 (35, 15.5) -> (34.5, 15) centre (35, 15) ccw
  arc A3 (34.5, 13) -> (35, 12.5) centre (35, 13) ccw
extrude "Volume menos haste" add sketch "Esboço3 (5)" against normal blind 5.4 bodies 10 in component "06 / Volume + e - / teclas no topo"
ref_plane "Plano de trabalho4" through (0, 56.5, 0) normal (0, 1, 0) x (0, 0, 1) in component "06 / Volume + e - / teclas no topo"
sketch "Esboço4 (4)" plane through (0, 56.5, 0) normal (0, 1, 0) x (1, 0, 0) in component "06 / Volume + e - / teclas no topo"
  line L0 (34.5, 13.7) -> (37.5, 13.7)
  line L1 (37.75, 13.95) -> (37.75, 14.05)
  line L2 (37.5, 14.3) -> (34.5, 14.3)
  line L3 (34.25, 14.05) -> (34.25, 13.95)
  arc A0 (37.5, 13.7) -> (37.75, 13.95) centre (37.5, 13.95) ccw
  arc A1 (37.75, 14.05) -> (37.5, 14.3) centre (37.5, 14.05) ccw
  arc A2 (34.5, 14.3) -> (34.25, 14.05) centre (34.5, 14.05) ccw
  arc A3 (34.25, 13.95) -> (34.5, 13.7) centre (34.5, 13.95) ccw
extrude "Volume menos sinal horizontal" cut sketch "Esboço4 (4)" against normal blind 0.35 bodies 10 in component "06 / Volume + e - / teclas no topo"
ref_plane "Plano de trabalho5" through (0, 56.4, 0) normal (0, 1, 0) x (0, 0, 1) in component "06 / Volume + e - / teclas no topo"
sketch "Esboço5 (4)" plane through (0, 56.4, 0) normal (0, 1, 0) x (1, 0, 0) in component "06 / Volume + e - / teclas no topo"
  line L0 (52.9, 10.5) -> (55.1, 10.5)
  line L1 (58.5, 13.9) -> (58.5, 14.1)
  line L2 (55.1, 17.5) -> (52.9, 17.5)
  line L3 (49.5, 14.1) -> (49.5, 13.9)
  arc A0 (55.1, 10.5) -> (58.5, 13.9) centre (55.1, 13.9) ccw
  arc A1 (58.5, 14.1) -> (55.1, 17.5) centre (55.1, 14.1) ccw
  arc A2 (52.9, 17.5) -> (49.5, 14.1) centre (52.9, 14.1) ccw
  arc A3 (49.5, 13.9) -> (52.9, 10.5) centre (52.9, 13.9) ccw
extrude "Volume mais" add sketch "Esboço5 (4)" against normal blind 3.1 separate body makes body 11 in component "06 / Volume + e - / teclas no topo"
ref_plane "Plano de trabalho6" through (0, 53.7, 0) normal (0, 1, 0) x (0, 0, 1) in component "06 / Volume + e - / teclas no topo"
sketch "Esboço6 (3)" plane through (0, 53.7, 0) normal (0, 1, 0) x (1, 0, 0) in component "06 / Volume + e - / teclas no topo"
  line L0 (50, 9) -> (58, 9)
  line L1 (60, 11) -> (60, 17)
  line L2 (58, 19) -> (50, 19)
  line L3 (48, 17) -> (48, 11)
  arc A0 (58, 9) -> (60, 11) centre (58, 11) ccw
  arc A1 (60, 17) -> (58, 19) centre (58, 17) ccw
  arc A2 (50, 19) -> (48, 17) centre (50, 17) ccw
  arc A3 (48, 11) -> (50, 9) centre (50, 11) ccw
extrude "Volume mais flange" add sketch "Esboço6 (3)" against normal blind 1.2 bodies 11 in component "06 / Volume + e - / teclas no topo"
ref_plane "Plano de trabalho7" through (0, 53, 0) normal (0, 1, 0) x (0, 0, 1) in component "06 / Volume + e - / teclas no topo"
sketch "Esboço7 (2)" plane through (0, 53, 0) normal (0, 1, 0) x (1, 0, 0) in component "06 / Volume + e - / teclas no topo"
  line L0 (53, 12.5) -> (55, 12.5)
  line L1 (55.5, 13) -> (55.5, 15)
  line L2 (55, 15.5) -> (53, 15.5)
  line L3 (52.5, 15) -> (52.5, 13)
  arc A0 (55, 12.5) -> (55.5, 13) centre (55, 13) ccw
  arc A1 (55.5, 15) -> (55, 15.5) centre (55, 15) ccw
  arc A2 (53, 15.5) -> (52.5, 15) centre (53, 15) ccw
  arc A3 (52.5, 13) -> (53, 12.5) centre (53, 13) ccw
extrude "Volume mais haste" add sketch "Esboço7 (2)" against normal blind 5.4 bodies 11 in component "06 / Volume + e - / teclas no topo"
ref_plane "Plano de trabalho8" through (0, 56.5, 0) normal (0, 1, 0) x (0, 0, 1) in component "06 / Volume + e - / teclas no topo"
sketch "Esboço8 (2)" plane through (0, 56.5, 0) normal (0, 1, 0) x (1, 0, 0) in component "06 / Volume + e - / teclas no topo"
  line L0 (52.5, 13.7) -> (55.5, 13.7)
  line L1 (55.75, 13.95) -> (55.75, 14.05)
  line L2 (55.5, 14.3) -> (52.5, 14.3)
  line L3 (52.25, 14.05) -> (52.25, 13.95)
  arc A0 (55.5, 13.7) -> (55.75, 13.95) centre (55.5, 13.95) ccw
  arc A1 (55.75, 14.05) -> (55.5, 14.3) centre (55.5, 14.05) ccw
  arc A2 (52.5, 14.3) -> (52.25, 14.05) centre (52.5, 14.05) ccw
  arc A3 (52.25, 13.95) -> (52.5, 13.7) centre (52.5, 13.95) ccw
extrude "Volume mais sinal horizontal" cut sketch "Esboço8 (2)" against normal blind 0.35 bodies 11 in component "06 / Volume + e - / teclas no topo"
ref_plane "Plano de trabalho9" through (0, 56.5, 0) normal (0, 1, 0) x (0, 0, 1) in component "06 / Volume + e - / teclas no topo"
sketch "Esboço9" plane through (0, 56.5, 0) normal (0, 1, 0) x (1, 0, 0) in component "06 / Volume + e - / teclas no topo"
  line L0 (53.95, 12.25) -> (54.05, 12.25)
  line L1 (54.3, 12.5) -> (54.3, 15.5)
  line L2 (54.05, 15.75) -> (53.95, 15.75)
  line L3 (53.7, 15.5) -> (53.7, 12.5)
  arc A0 (54.05, 12.25) -> (54.3, 12.5) centre (54.05, 12.5) ccw
  arc A1 (54.3, 15.5) -> (54.05, 15.75) centre (54.05, 15.5) ccw
  arc A2 (53.95, 15.75) -> (53.7, 15.5) centre (53.95, 15.5) ccw
  arc A3 (53.7, 12.5) -> (53.95, 12.25) centre (53.95, 12.5) ccw
extrude "Volume mais sinal vertical" cut sketch "Esboço9" against normal blind 0.35 bodies 11 in component "06 / Volume + e - / teclas no topo"
ref_plane "Plano de trabalho1" through (0, 46.3, 0) normal (0, 1, 0) x (0, 0, 1) in component "07 / Suporte dos switches volume / eletrica pendente"
sketch "Esboço1 (8)" plane through (0, 46.3, 0) normal (0, 1, 0) x (1, 0, 0) in component "07 / Suporte dos switches volume / eletrica pendente"
  line L0 (30, 6) -> (60, 6)
  line L1 (62, 8) -> (62, 20)
  line L2 (60, 22) -> (30, 22)
  line L3 (28, 20) -> (28, 8)
  arc A0 (60, 6) -> (62, 8) centre (60, 8) ccw
  arc A1 (62, 20) -> (60, 22) centre (60, 20) ccw
  arc A2 (30, 22) -> (28, 20) centre (30, 20) ccw
  arc A3 (28, 8) -> (30, 6) centre (30, 8) ccw
extrude "Suporte tact switches" add sketch "Esboço1 (8)" against normal blind 2.4 separate body makes body 12 in component "07 / Suporte dos switches volume / eletrica pendente"
ref_plane "Plano de trabalho2" through (0, 46.4, 0) normal (0, 1, 0) x (0, 0, 1) in component "07 / Suporte dos switches volume / eletrica pendente"
sketch "Esboço2 (8)" plane through (0, 46.4, 0) normal (0, 1, 0) x (1, 0, 0) in component "07 / Suporte dos switches volume / eletrica pendente"
  line L0 (33.2, 10.8) -> (38.8, 10.8)
  line L1 (39.2, 11.2) -> (39.2, 16.8)
  line L2 (38.8, 17.2) -> (33.2, 17.2)
  line L3 (32.8, 16.8) -> (32.8, 11.2)
  arc A0 (38.8, 10.8) -> (39.2, 11.2) centre (38.8, 11.2) ccw
  arc A1 (39.2, 16.8) -> (38.8, 17.2) centre (38.8, 16.8) ccw
  arc A2 (33.2, 17.2) -> (32.8, 16.8) centre (33.2, 16.8) ccw
  arc A3 (32.8, 11.2) -> (33.2, 10.8) centre (33.2, 11.2) ccw
extrude "Nicho tact switch" cut sketch "Esboço2 (8)" against normal blind 1.1 bodies 12 in component "07 / Suporte dos switches volume / eletrica pendente"
ref_plane "Plano de trabalho3" through (0, 46.4, 0) normal (0, 1, 0) x (0, 0, 1) in component "07 / Suporte dos switches volume / eletrica pendente"
sketch "Esboço3 (6)" plane through (0, 46.4, 0) normal (0, 1, 0) x (1, 0, 0) in component "07 / Suporte dos switches volume / eletrica pendente"
  line L0 (51.2, 10.8) -> (56.8, 10.8)
  line L1 (57.2, 11.2) -> (57.2, 16.8)
  line L2 (56.8, 17.2) -> (51.2, 17.2)
  line L3 (50.8, 16.8) -> (50.8, 11.2)
  arc A0 (56.8, 10.8) -> (57.2, 11.2) centre (56.8, 11.2) ccw
  arc A1 (57.2, 16.8) -> (56.8, 17.2) centre (56.8, 16.8) ccw
  arc A2 (51.2, 17.2) -> (50.8, 16.8) centre (51.2, 16.8) ccw
  arc A3 (50.8, 11.2) -> (51.2, 10.8) centre (51.2, 11.2) ccw
extrude "Nicho tact switch (1)" cut sketch "Esboço3 (6)" against normal blind 1.1 bodies 12 in component "07 / Suporte dos switches volume / eletrica pendente"
ref_plane "Plano de trabalho1" through (88.2, 0, 0) normal (1, 0, 0) x (0, 1, 0) in component "08 / Cursor lateral ON OFF / aciona chave da placa"
sketch "Esboço1 (9)" plane through (88.2, 0, 0) normal (1, 0, 0) x (0, 0, -1) in component "08 / Cursor lateral ON OFF / aciona chave da placa"
  line L0 (7.9, 32.82) -> (10.1, 32.82)
  line L1 (12.3, 35.02) -> (12.3, 40.62)
  line L2 (10.1, 42.82) -> (7.9, 42.82)
  line L3 (5.7, 40.62) -> (5.7, 35.02)
  arc A0 (10.1, 32.82) -> (12.3, 35.02) centre (10.1, 35.02) ccw
  arc A1 (12.3, 40.62) -> (10.1, 42.82) centre (10.1, 40.62) ccw
  arc A2 (7.9, 42.82) -> (5.7, 40.62) centre (7.9, 40.62) ccw
  arc A3 (5.7, 35.02) -> (7.9, 32.82) centre (7.9, 35.02) ccw
extrude "Tecla externa ON OFF" add sketch "Esboço1 (9)" along normal blind 1.7 separate body makes body 13 in component "08 / Cursor lateral ON OFF / aciona chave da placa"
ref_plane "Plano de trabalho2" through (83, 0, 0) normal (1, 0, 0) x (0, 1, 0) in component "08 / Cursor lateral ON OFF / aciona chave da placa"
sketch "Esboço2 (9)" plane through (83, 0, 0) normal (1, 0, 0) x (0, 0, -1) in component "08 / Cursor lateral ON OFF / aciona chave da placa"
  line L0 (7.5, 35.32) -> (10.5, 35.32)
  line L1 (11, 35.82) -> (11, 39.82)
  line L2 (10.5, 40.32) -> (7.5, 40.32)
  line L3 (7, 39.82) -> (7, 35.82)
  arc A0 (10.5, 35.32) -> (11, 35.82) centre (10.5, 35.82) ccw
  arc A1 (11, 39.82) -> (10.5, 40.32) centre (10.5, 39.82) ccw
  arc A2 (7.5, 40.32) -> (7, 39.82) centre (7.5, 39.82) ccw
  arc A3 (7, 35.82) -> (7.5, 35.32) centre (7.5, 35.82) ccw
extrude "Ponte do cursor ate a chave" add sketch "Esboço2 (9)" along normal blind 6 bodies 13 in component "08 / Cursor lateral ON OFF / aciona chave da placa"
ref_plane "Plano de trabalho3" through (85, 0, 0) normal (1, 0, 0) x (0, 1, 0) in component "08 / Cursor lateral ON OFF / aciona chave da placa"
sketch "Esboço3 (7)" plane through (85, 0, 0) normal (1, 0, 0) x (0, 0, -1) in component "08 / Cursor lateral ON OFF / aciona chave da placa"
  line L0 (6, 28.82) -> (12, 28.82)
  line L1 (14, 30.82) -> (14, 44.82)
  line L2 (12, 46.82) -> (6, 46.82)
  line L3 (4, 44.82) -> (4, 30.82)
  arc A0 (12, 28.82) -> (14, 30.82) centre (12, 30.82) ccw
  arc A1 (14, 44.82) -> (12, 46.82) centre (12, 44.82) ccw
  arc A2 (6, 46.82) -> (4, 44.82) centre (6, 44.82) ccw
  arc A3 (4, 30.82) -> (6, 28.82) centre (6, 30.82) ccw
extrude "Flange de retencao" add sketch "Esboço3 (7)" along normal blind 1.2 bodies 13 in component "08 / Cursor lateral ON OFF / aciona chave da placa"
ref_plane "Plano de trabalho4" through (82, 0, 0) normal (1, 0, 0) x (0, 1, 0) in component "08 / Cursor lateral ON OFF / aciona chave da placa"
sketch "Esboço4 (5)" plane through (82, 0, 0) normal (1, 0, 0) x (0, 0, -1) in component "08 / Cursor lateral ON OFF / aciona chave da placa"
  line L0 (7.5, 35.32) -> (10.5, 35.32)
  line L1 (11, 35.82) -> (11, 39.82)
  line L2 (10.5, 40.32) -> (7.5, 40.32)
  line L3 (7, 39.82) -> (7, 35.82)
  arc A0 (10.5, 35.32) -> (11, 35.82) centre (10.5, 35.82) ccw
  arc A1 (11, 39.82) -> (10.5, 40.32) centre (10.5, 39.82) ccw
  arc A2 (7.5, 40.32) -> (7, 39.82) centre (7.5, 39.82) ccw
  arc A3 (7, 35.82) -> (7.5, 35.32) centre (7.5, 35.82) ccw
extrude "Garfo chave / medir lingueta" add sketch "Esboço4 (5)" along normal blind 2.2 bodies 13 in component "08 / Cursor lateral ON OFF / aciona chave da placa"
ref_plane "Plano de trabalho5" through (81.9, 0, 0) normal (1, 0, 0) x (0, 1, 0) in component "08 / Cursor lateral ON OFF / aciona chave da placa"
sketch "Esboço5 (5)" plane through (81.9, 0, 0) normal (1, 0, 0) x (0, 0, -1) in component "08 / Cursor lateral ON OFF / aciona chave da placa"
  line L0 (8.3, 36.82) -> (9.7, 36.82)
  line L1 (10, 37.12) -> (10, 38.52)
  line L2 (9.7, 38.82) -> (8.3, 38.82)
  line L3 (8, 38.52) -> (8, 37.12)
  arc A0 (9.7, 36.82) -> (10, 37.12) centre (9.7, 37.12) ccw
  arc A1 (10, 38.52) -> (9.7, 38.82) centre (9.7, 38.52) ccw
  arc A2 (8.3, 38.82) -> (8, 38.52) centre (8.3, 38.52) ccw
  arc A3 (8, 37.12) -> (8.3, 36.82) centre (8.3, 37.12) ccw
extrude "Rasgo para lingueta original" cut sketch "Esboço5 (5)" along normal blind 2.3 bodies 13 in component "08 / Cursor lateral ON OFF / aciona chave da placa"
ref_plane "Plano de trabalho1" through (0, 0, -3) normal (0, 0, 1) x (1, 0, 0) in component "09 / Bicos MIC frontais / dutos a medir"
sketch "Esboço1 (10)" plane through (0, 0, -3) normal (0, 0, 1) x (1, 0, 0) in component "09 / Bicos MIC frontais / dutos a medir"
  circle A0 centre (-68, -51) radius 1.8
  circle A1 centre (-68, -51) radius 1
extrude "Extrusão1" add sketch "Esboço1 (10)" against normal blind 3 separate body makes body 14 in component "09 / Bicos MIC frontais / dutos a medir"